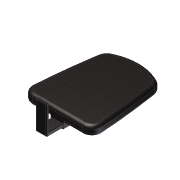
# Autodesk Inventor part: Naslon
Saved by Autodesk Inventor 2012 (Build 160160000, 160)
## iProperties
Created: 2009-08-13
Part Number: Naslon
Document SubType Name: Modeling
Designer: Milos Zaric
Density: 1 g/cm^3
Material: Default
Author: Milos Zaric
Autodesk Inventor part; units mm, degrees
ref_plane "YZ Plane" through (0, 0, 0) normal (1, 0, 0) x (0, 1, 0)
ref_plane "XZ Plane" through (0, 0, 0) normal (0, 1, 0) x (-1, 0, 0)
ref_plane "XY Plane" through (0, 0, 0) normal (0, 0, 1) x (1, 0, 0)
sketch "Sketch1" plane through (0, 0, 0) normal (0, 0, 1) x (1, 0, 0)
  line L0 (-24.2772, 481.7348) -> (415.7228, 481.7348)
  line L1 (351.9608, -28.2652) -> (39.4849, -28.2652)
  line L2 (195.7228, 481.7348) -> (195.7228, 269.9826)
  line L3 (25.7228, 481.7348) -> (25.7228, 431.7348)
  line L4 (365.7228, 481.7348) -> (365.7228, 431.7348)
  arc A0 (338.2638, 447.517) -> (53.1819, 447.517) centre (195.7228, 167.7348) ccw
  arc A1 (411.8203, 35.8386) -> (370.2929, 403.4102) centre (-3778.3444, -251.4247) ccw
  arc A2 (21.1528, 403.4102) -> (-20.3746, 35.8386) centre (4169.7901, -251.4247) ccw
  arc A3 (-20.3746, 35.8386) -> (39.4849, -28.2652) centre (39.4849, 31.7348) ccw
  arc A4 (351.9608, -28.2652) -> (411.8203, 35.8386) centre (351.9608, 31.7348) ccw
  arc A5 (370.2929, 403.4102) -> (338.2638, 447.517) centre (311.0266, 394.0554) ccw
  arc A6 (53.1819, 447.517) -> (21.1528, 403.4102) centre (80.419, 394.0554) ccw
  dimension "d4" = 50
  dimension "d5" = 50
  dimension "d6" = 4200
  dimension "d7" = 4200
  dimension "d8" = 60
  constraints: 19 point on circle, 10 end point, 8 tangent, 7 centre point, 3 equal radius, 3 parallel, 2 point on line, 1 horizontal, 1 midpoint
  measures "d4" distance of L3.start L3.end
  measures "d5" distance of L4.start L4.end
  measures "d6" radius of A1
  measures "d7" radius of A2
  measures "d8" radius of A3
extrude "Extrusion1" add sketch "Sketch1" along normal blind 60
sketch "Sketch2" plane through (0, 0, 0) normal (0, 0, -1) x (-1, 0, 0)
  arc A0 (-53.1819, 447.517) -> (-338.2638, 447.517) centre (-195.7228, 167.7348) ccw projected
  line L0 (-39.4849, -28.2652) -> (-351.9608, -28.2652) projected
  line L1 (-235.7228, 271.7348) -> (-155.7228, 271.7348)
  line L2 (-155.7228, 271.7348) -> (-155.7228, -28.2652)
  line L3 (-155.7228, -28.2652) -> (-235.7228, -28.2652)
  line L4 (-235.7228, -28.2652) -> (-235.7228, 271.7348)
  dimension "d11" = 40
  dimension "d12" = 40
  dimension "d13" = 300
  constraints: 8 end point, 2 parallel, 1 horizontal, 1 perpendicular, 1 point on line
  measures "d11" distance from line of L2 A0.centre
  measures "d12" distance from line of A0.centre L4
  measures "d13" distance of L1.end L2.end
extrude "Extrusion2" add sketch "Sketch2" along normal blind 30
fillet "Fillet1" radius 20 17 edges at (395.1052, 220.0818, 0) (359.5762, 429.3108, 0) (195.7228, 481.7348, 0) (31.8695, 429.3108, 0) (-3.6596, 220.0818, 0) (-4.3684, -9.215, 0) (97.6039, -28.2652, 0) (395.8141, -9.215, 0) (293.8418, -28.2652, 0) (395.1052, 220.0818, 60) (395.8141, -9.215, 60) (195.7228, -28.2652, 60) (-4.3684, -9.215, 60) (-3.6596, 220.0818, 60) (31.8695, 429.3108, 60) (195.7228, 481.7348, 60) (359.5762, 429.3108, 60)
fillet "Fillet2" radius 5 5 edges at (235.7228, 121.7348, -30) (155.7228, 121.7348, -30) (155.7228, 271.7348, -15) (235.7228, 271.7348, -15) (195.7228, 271.7348, -30)
fillet "Fillet3" radius 5 7 edges at (235.7228, 129.2348, 0) (234.2584, 270.2703, 0) (195.7228, 271.7348, 0) (157.1873, 270.2703, 0) (155.7228, 129.2348, 0) (155.7228, -22.4073, 5.8579) (235.7228, -22.4073, 5.8579)
sketch "Sketch3" plane through (39.4849, -28.2652, 40) normal (0, -1, 0) x (1, 0, 0)
  arc A0 (116.2379, -65) -> (121.2379, -70) centre (121.2379, -65) ccw projected
  line L0 (121.2379, -65) -> (191.2379, -65)
  line L1 (191.2379, -65) -> (191.2379, -40.0176)
  line L2 (191.2379, -40.0176) -> (121.2379, -40.0176)
  line L3 (121.2379, -40.0176) -> (121.2379, -65)
  constraints: 8 end point, 2 parallel, 1 horizontal, 1 perpendicular
extrude "Extrusion3" add sketch "Sketch3" along normal blind 100
sketch "Sketch4" plane through (160.7228, -28.2652, -0.0176) normal (0, 0, 1) x (1, 0, 0)
  line L0 (0, -100) -> (70, -100) projected
  line L1 (70, 0) -> (70, -100) projected
  line L2 (0, 0) -> (0, -100) projected
  line L3 (0, -100) -> (70, -100)
  line L4 (70, -100) -> (70, -85.2025)
  line L5 (70, -85.2025) -> (0, -85.2025)
  line L6 (0, -85.2025) -> (0, -100)
  dimension "d21" = 0
  constraints: 8 end point, 2 parallel, 2 point on line, 1 horizontal, 1 perpendicular
  measures "d21" distance between parallel lines of L6 L2
extrude "Extrusion4" add sketch "Sketch4" along normal blind 150
fillet "Fillet4" radius 5 9 edges at (230.7228, -78.2652, -25) (160.7228, -78.2652, -25) (195.7228, -128.2652, -25) (160.7228, -128.2652, 62.4912) (160.7228, -113.4677, 74.9824) (160.7228, -70.8664, -0.0176) (230.7228, -70.8664, -0.0176) (230.7228, -113.4677, 74.9824) (230.7228, -128.2652, 62.4912)
body "Solid1"
